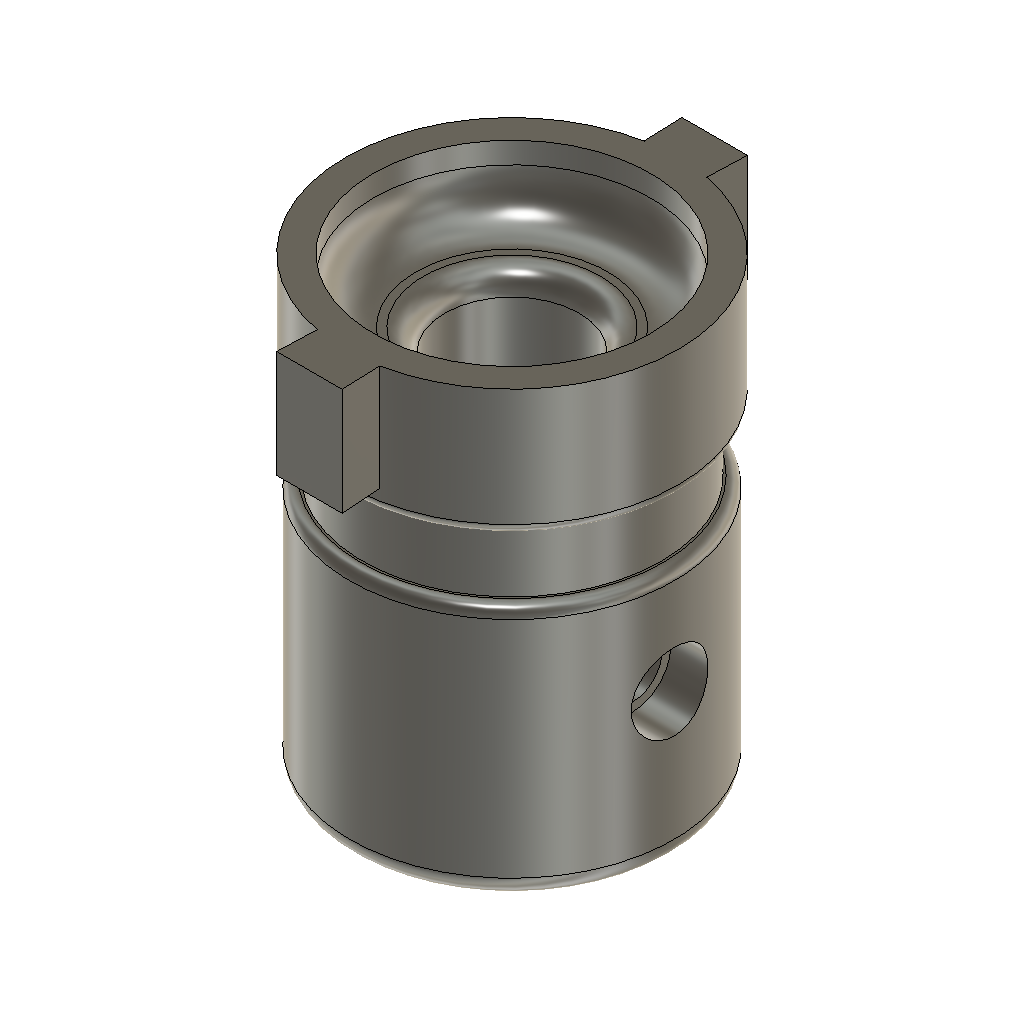
W461_light_distance_switch_adapter (Autodesk Fusion 360 design; units mm, degrees)
part number: 2026-11-12-17-12-32-783
Autodesk Fusion 360 part; units mm, degrees
note: some values were not read from the file. Set by a fixed rule: which face or edge a step refers to.
sketch "Sketch1" plane through (0, 0, 0) normal (0, 0, 1) x (1, 0, 0)
  circle A0 centre (0, 0) radius 7.5
  dimension "d1" = 15
  constraint coincident A0.centre origin
  measures "d1" diameter of A0
extrude "Extrude1" add sketch "Sketch1" along normal blind 20 makes body 1
ref_plane "WorkPlane1" through (0, 0, 2) normal (0, 0, -1) x (-1, 0, 0)
sketch "Sketch2" plane through (0, 0, 2) normal (0, 0, -1) x (-1, 0, 0)
  circle A0 centre (0, 0) radius 7.5
  circle A1 centre (0, 0) radius 7
  dimension "d6" = 15
  dimension "d7" = 14
  constraint coincident A0.centre A1.centre
  measures "d6" diameter of A0
  measures "d7" diameter of A1
extrude "Extrude2" cut sketch "Sketch2" against normal blind 3 bodies 1
sketch "Sketch3" plane through (0, 0, 20) normal (0, 0, 1) x (-1, 0, 0)
  circle A0 centre (0, 0) radius 7.5
  circle A1 centre (0, 0) radius 3.15
  dimension "d10" = 6.3
  constraint coincident A0.centre A1.centre
  measures "d10" diameter of A1
extrude "Extrude3" cut sketch "Sketch3" against normal blind 26 contours A1 bodies 1
ref_plane "WorkPlane2" through (7.5, 0, 15.5254) normal (1, 0, 0) x (0, -1, 0)
move_face "OffsetFaces1" offset 1 1 faces at (7.4627, 0.7468, 10) on bodies 1
extrude "Extrude6" cut 1 faces at (6.6733, 0.5788, 20) along direction (0, 0, -1) blind 5 on bodies 1 bodies 1
move_face "OffsetFaces2" offset 1.3 1 faces at (7.4907, 0.3738, 0.6667) on bodies 1
extrude "Extrude7" add 1 faces at (6.8839, 0.4372, 0) along direction (0, 0, -1) blind 5 on bodies 1 bodies 1
ref_plane "WorkPlane3" through (0, 8.5, 11.4067) normal (0, 1, 0) x (1, 0, 0)
sketch "Sketch5" plane through (0, 8.5, 0) normal (0, 1, 0) x (1, 0, 0)
  line L0 (-1.5, -7) -> (1.5, -7)
  line L1 (1.5, -7) -> (1.5, -15)
  line L2 (1.5, -15) -> (-1.5, -15)
  line L3 (-1.5, -15) -> (-1.5, -7)
  line L4 (0, 0) -> (0, -18) construction
  dimension "d44" = 3
  dimension "d45" = 8
  dimension "d46" = 1.5
  constraint horizontal L0
  constraint vertical L1
  constraint horizontal L2
  constraint vertical L3
  constraint coincident L4.start origin
  constraint perpendicular L0 L4
  measures "d44" distance of L0.start L0.end
  measures "d45" distance of L0.start L2.end
  measures "d46" distance of L3 L4
extrude "Extrude8" add sketch "Sketch5" along normal blind 2 draft 2 and the other way blind 1 separate body makes body 2
mirror "Mirror1" about plane through (0, 0, 0) normal (0, 1, 0) of bodies 2 makes body 3
extrude "Extrude9" cut 1 faces at (6.6733, 0.5788, 15) along direction (0, 0, -1) blind 4 on bodies 1 bodies 1 3
move_body "Move1" bodies 3 to x (1, 0, 0) y (0, 1, 0) z (0, 0, 1) at (0, 0, -1)
move_body "Move2" bodies 2 to x (1, 0, 0) y (0, 1, 0) z (0, 0, 1) at (0, 0, -1)
combine "Combine2" operation add target body 1 tool bodies 2 3
ref_plane "WorkPlane4" through (0, 0, 22) normal (0, 0, 1) x (1, 0, 0)
sketch "Sketch6" plane through (0, 0, 22) normal (0, 0, 1) x (1, 0, 0)
  line L0 (-11.8815, 12.7365) -> (12.2943, 12.7365)
  line L1 (12.2943, 12.7365) -> (12.2943, -14.1222)
  line L2 (12.2943, -14.1222) -> (-11.8815, -14.1222)
  line L3 (-11.8815, -14.1222) -> (-11.8815, 12.7365)
  constraint horizontal L0
  constraint vertical L1
  constraint horizontal L2
  constraint vertical L3
extrude "Extrude10" cut sketch "Sketch6" against normal blind 11 bodies 1
delete_face "DeleteFace1" 1 faces at (1.5, -8.4555, 7.6667) on bodies 1
delete_face "DeleteFace2" 1 faces at (-1.5, -8.4555, 9.3333) on bodies 1
delete_face "DeleteFace3" 1 faces at (-1.5, 8.4555, 9.3333) on bodies 1
delete_face "DeleteFace4" 1 faces at (1.5, 8.4555, 7.6667) on bodies 1
delete_face "DeleteFace5" 1 faces at (-1.3317, 8.4361, 6) on bodies 1
delete_face "DeleteFace6" 1 faces at (1.3317, 8.4361, 6) on bodies 1
delete_face "DeleteFace7" 1 faces at (1.3317, -8.4361, 6) on bodies 1
delete_face "DeleteFace8" 1 faces at (-1.3317, -8.4361, 6) on bodies 1
move_face "OffsetFaces4" offset -0.7 1 faces at (8.7891, 0.4386, -2.6667) on bodies 1
move_face "OffsetFaces5" offset -0.7 1 faces at (-2.4426, -8.1415, 7.3349) on bodies 1
extrude "Extrude11" cut 1 faces at (-0.5233, -10.5, 7.6201) along direction (0, 1, 0) blind 1 on bodies 1 bodies 1
extrude "Extrude12" cut 1 faces at (-0.5233, 10.5, 7.6201) along direction (0, -1, 0) blind 1 on bodies 1 bodies 1
extrude "Extrude13" add 1 faces at (6.4198, 0.4024, -5) along direction (0, 0, -1) blind 5 on bodies 1 bodies 1
fillet "Fillet19" radius 0.5 1 edges at (-7.2722, -2.8206, 5) on bodies 1
ref_plane "WorkPlane5" through (8.1, 0, -4.6235) normal (1, 0, 0) x (0, -1, 0)
sketch "Sketch7" plane through (8.1, 0, 0) normal (1, 0, 0) x (0, 1, 0)
  circle A0 centre (0, -3) radius 1.4
  circle A1 centre (0, -3) radius 1.8
  dimension "d93" = 2.8
  dimension "d94" = 3.6
  constraint concentric A0 A1
  measures "d93" diameter of A0
  measures "d94" diameter of A1
extrude "Extrude14" cut sketch "Sketch7" against normal blind 2.5 bodies 1
extrude "Extrude15" cut sketch "Sketch7" against normal blind 19 contours A0 bodies 1
sketch "Sketch8" plane through (0, 0, -10) normal (0, 0, -1) x (1, 0, 0)
  circle A0 centre (0, 0) radius 3.15
  circle A1 centre (0, 0) radius 8.1
move_face "OffsetFaces6" offset -0.5 1 faces at (7.5404, -2.9585, -3.6667) on bodies 1
fillet "Fillet20" radius 0.5 1 edges at (-7.0857, 2.7483, 2) on bodies 1
fillet "Fillet21" radius 1 1 edges at (-7.0857, 2.7483, -10) on bodies 1
sketch "Sketch9" plane through (0, 0, 11) normal (0, 0, 1) x (-1, 0, 0)
  line L0 (-1.5349, -9.5) -> (1.5349, -9.5)
  line L1 (1.5349, -9.5) -> (1.4707, -7.6601)
  arc A0 (1.4707, -7.6601) -> (1.4707, 7.6601) centre (0, 0) ccw
  line L2 (1.4707, 7.6601) -> (1.5349, 9.5)
  line L3 (1.5349, 9.5) -> (-1.5349, 9.5)
  line L4 (-1.5349, 9.5) -> (-1.4707, 7.6601)
  arc A1 (-1.4707, 7.6601) -> (-1.4707, -7.6601) centre (0, 0) ccw
  line L5 (-1.4707, -7.6601) -> (-1.5349, -9.5)
  circle A2 centre (0, 0) radius 3.15
  circle A3 centre (0, 0) radius 6.5
  dimension "d104" = 13
  constraint coincident A0.centre A1.centre
  measures "d104" diameter of A3
extrude "Extrude16" cut sketch "Sketch9" against normal blind 3 contours A3 bodies 1
fillet "Fillet22" radius 1 1 edges at (2.9368, 1.1391, 8) on bodies 1
fillet "Fillet23" radius 2 1 edges at (6.0601, -2.3505, 8) on bodies 1
extrude "Extrude17" add 1 faces at (5.6, 1.6548, -3.159) along direction (1, 0, 0) blind 0.05 on bodies 1 bodies 1
other "Mirror1'"
sketch "Sketch10" plane through (-8.1, 0, 0) normal (-1, 0, 0) x (0, -1, 0)
  circle A0 centre (0, -3) radius 1.8
  dimension "d114" = 3.6
  measures "d114" diameter of A0
extrude "Extrude18" cut sketch "Sketch10" against normal blind 3 bodies 1
extrude "Extrude19" add 1 faces at (-5.1, -1.6548, -3.159) along direction (-1, 0, 0) blind 0.55 on bodies 1 bodies 1
